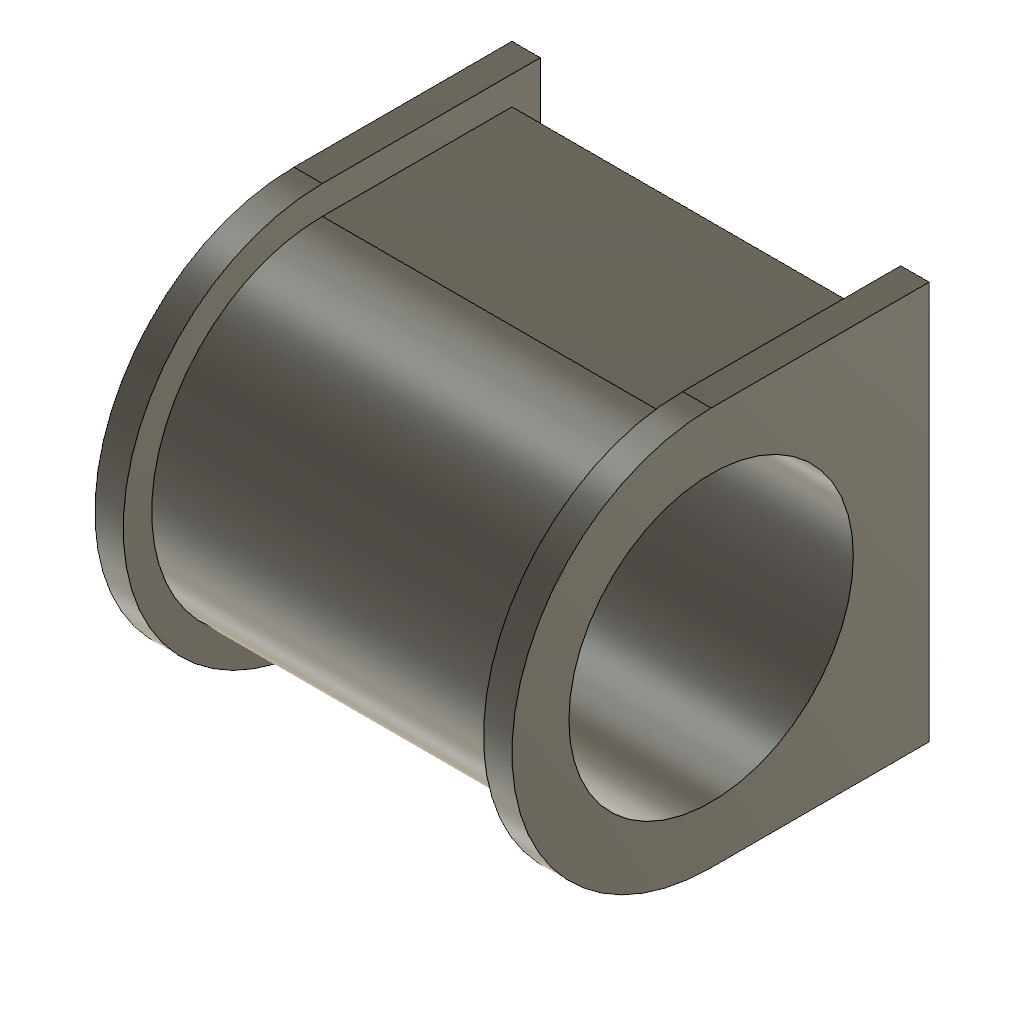
brasses (Autodesk Fusion 360 design; units mm, degrees)
part number: 2026-10-08-14-32-37-990
Autodesk Fusion 360 part; units mm, degrees
sketch "Sketch1" plane through (0, 0, 0) normal (1, 0, 0) x (0, 1, 0)
  circle A0 centre (0, 0) radius 30
  line L0 (0, 36) -> (40, 36)
  line L1 (0, 42) -> (46, 42)
  line L2 (0, -36) -> (40, -36)
  line L3 (0, -42) -> (46, -42)
  line L4 (40, 36) -> (40, -36)
  line L5 (46, 42) -> (46, -42)
  arc A1 (0, 36) -> (0, -36) centre (0, 0) ccw
  arc A2 (0, 42) -> (0, -42) centre (0, 0) ccw
  dimension "d1" = 60
  dimension "d2" = 72
  dimension "d3" = 84
  dimension "d4" = 40
  dimension "d5" = 46
  dimension "d6" = 40
  dimension "d7" = 46
  constraint coincident A0.centre A1.centre
  constraint horizontal L0
  constraint horizontal L1
  constraint horizontal L2
  constraint horizontal L3
  constraint tangent L0 A1
  constraint tangent L1 A2
  constraint tangent L2 A1
  constraint tangent L3 A2
  measures "d1" diameter of A0
  measures "d2" diameter of A1
  measures "d3" diameter of A2
  measures "d4" distance of L0.start L0.end
  measures "d5" distance of L1.start L1.end
  measures "d6" distance of L2.start L2.end
  measures "d7" distance of L3.start L3.end
extrude "Extrude1" add sketch "Sketch1" along normal blind 76 contours L0 L2 L4 A1 makes body 1
sketch "Sketch2" plane through (76, 0, 0) normal (1, 0, 0) x (0, 1, 0)
  circle A0 centre (0, 0) radius 30
  line L0 (40, 36) -> (0, 36)
  arc A1 (0, 36) -> (0, -36) centre (0, 0) ccw
  line L1 (0, -36) -> (40, -36)
  line L2 (40, -36) -> (40, 36)
  line L3 (0, 42) -> (46, 42)
  line L4 (0, -42) -> (46, -42)
  line L5 (46, 42) -> (46, -42)
  arc A2 (0, 42) -> (0, -42) centre (0, 0) ccw
  dimension "d10" = 84
  dimension "d11" = 46
  dimension "d12" = 46
  constraint concentric A0 A2
  constraint perpendicular L2 L3
  constraint parallel L1 L4
  constraint tangent L3 A2
  constraint tangent L4 A2
  measures "d10" diameter of A2
  measures "d11" distance of L3.start L3.end
  measures "d12" distance of L4.start L4.end
extrude "Extrude2" add sketch "Sketch2" along normal blind 6 separate body contours L3 L4 L5 A2 makes body 2
extrude "Extrude3" add 1 faces at (76, 36.6667, 0) along direction (1, 0, 0) blind 6 on bodies 1 bodies 1 2
sketch "Sketch3" plane through (0, 0, 0) normal (-1, 0, 0) x (0, -1, 0)
  circle A0 centre (0, 0) radius 30
  line L0 (0, 36) -> (-40, 36)
  line L1 (-40, 36) -> (-40, -36)
  line L2 (-40, -36) -> (0, -36)
  arc A1 (0, -36) -> (0, 36) centre (0, 0) ccw
  line L3 (0, 42) -> (-46, 42)
  line L4 (-46, 42) -> (-46, -42)
  line L5 (-46, -42) -> (0, -42)
  arc A2 (0, -42) -> (0, 42) centre (0, 0) ccw
  dimension "d17" = 84
  dimension "d18" = 46
  dimension "d19" = 84
  constraint concentric A0 A2
  constraint horizontal L3
  constraint vertical L4
  constraint horizontal L5
  measures "d17" diameter of A2
  measures "d18" distance of L3.start L3.end
  measures "d19" distance of L3.start L5.end
extrude "Extrude4" add sketch "Sketch3" along normal blind 6 contours L0 L1 L2 A1 | L3 L4 L5 A2 bodies 1
